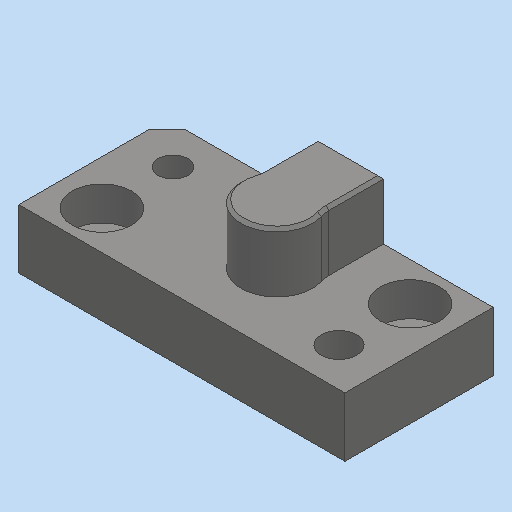
# Autodesk Inventor part: MM0948AN160_G01_155
Saved by Autodesk Inventor 2023.3 (Build 273359000, 359)
## iProperties
RuleStatus: InUse
Created: 2023-04-14
Part Number: MM0948AN160_G01_155
Material: 1.2379 X155CrVMo12-1
Description: =<RBPARTNOTITLE2>
Document SubType Name: Modeling
Designer: ric7an
Mass: 110.504 g
Surface Area: 55.1793 cm^2
Volume: 14.0769 cm^3
Density: 7.85 g/cm^3
Appearance: Stahl - rostfrei AnP
AnP_Kategorie: 1
AnP_Material: =<Material>
MaxAbmaße: 20 x 25 x 55 (FM)
AnP_TemplVers: 20200821
RBDOCUMENTTYPE: DRF
RBDOCUMENTVERSION: 00
RBDRAWINGMAINSCALE: 1:1
RBDRAWINGMISSINGSPEC: --
RBDRAWINGVOLUME: --
RBDSV1: 0850
RBGBEDGESIN1: +0,5
RBGBEDGESIN2: +0,2
RBGBEDGESOUT1: -0,3
RBGBEDGESOUT2: -0,1
RBMATERIAL: =<Material>
RBMATMEETS: --
RBMATNO: =<Part Number>
RBPARTMADEOF: 20 x 25 x 55 (FM)
RBPARTNO: SIEHE MNR
RBPARTNOTITLE1: manufactured part
RBPARTNOTITLE2: Anfertigungsteil
RBPARTSAFETYINDICATOR: --
RBSURFACE: vaccum hardened 58 HRC ± 1
RBSURFACE2: vakuumgehaertet 58 HRC ± 1
RBZEDGESNORM: ISO13715:2002-06
RBZGENDIMCLASS: m
RBZGENDIMNORM: ISO 2768-1:1989-11
RBZGENGEOCLASS: H
RBZGENGEONORM: ISO 2768-2:1989-11
RBZSURFACENORM: ISO13D2:2002-02
RBZTOLERANCENORM: ISO 14405-1:2010-12
Author: ric7an
Keywords: =<RBPARTMADEOF>
Comments: =<RBSURFACE2>
Revision Number: 01
Autodesk Inventor part; units mm, degrees
ref_plane "YZ Plane" through (0, 0, 0) normal (1, 0, 0) x (0, 1, 0)
ref_plane "XZ Plane" through (0, 0, 0) normal (0, 1, 0) x (-1, 0, 0)
ref_plane "XY Plane" through (0, 0, 0) normal (0, 0, 1) x (1, 0, 0)
sketch "Skizze1" plane through (0, 0, 0) normal (0, 0, 1) x (1, 0, 0)
  line L0 (-27.5, 12.5) -> (27.5, 12.5)
  line L1 (27.5, 12.5) -> (27.5, -12.5)
  line L2 (27.5, -12.5) -> (-27.5, -12.5)
  line L3 (-27.5, -12.5) -> (-27.5, 12.5)
  line L4 (0, 17.5) -> (0, -17.5) projected
  line L5 (-38.5, 0) -> (38.5, 0) projected
  point P0 (0, 0)
  dimension "d0" = 55
  dimension "d1" = 25
  constraints: 8 end point, 2 parallel, 1 horizontal, 1 perpendicular, 2 other
  measures "d0" distance of L0.start L0.end
  measures "d1" distance of L0.end L1.end
extrude "Extrusion1" add sketch "Skizze1" along normal blind 10
sketch "Skizze2" plane through (0, 0, 10) normal (0, 0, 1) x (1, 0, 0)
  line L0 (0, 17.5) -> (0, -17.5) projected
  line L1 (-38.5, 0) -> (38.5, 0) projected
  point P0 (0, 0)
  point P1 (-20, -6)
  point P2 (20, 6)
  dimension "d4" = 40
  dimension "d5" = 20
  dimension "d6" = 12
  dimension "d7" = 6
  measures "d4" horizontal distance of point (20, 6) point (-20, -6)
  measures "d5" distance from line of L0 point (-20, -6)
  measures "d6" vertical distance of point (20, 6) point (-20, -6)
  measures "d7" distance from line of L1 point (-20, -6)
hole "Bohrung1" at (-20, -6, 10) at (20, 6, 10) direction (0, 0, -1) diameter 5.5 end through all counterbore diameter 10 counterbore depth 5.7 clearance for "Inbusschraube ISO 4762  versenkt" size "M5" standard "ISO"
sketch "Skizze3" plane through (0, 0, 10) normal (0, 0, 1) x (1, 0, 0)
  circle A0 centre (-20, -6) radius 5 projected
  circle A1 centre (20, 6) radius 5 projected
  point P0 (0, 0)
  point P1 (-20, 6)
  constraints: 1 horizontal alignment, 1 vertical alignment
hole "Bohrung2" at (-20, 6, 10) direction (0, 0, -1) diameter 5 end through all
sketch "Skizze4" plane through (0, 0, 10) normal (0, 0, 1) x (1, 0, 0)
  circle A0 centre (-20, 6) radius 2.5 projected
  circle A1 centre (-20, -6) radius 5 projected
  circle A2 centre (20, 6) radius 5 projected
  line L0 (27.5, -12.5) -> (27.5, 12.5) projected
  line L1 (27.5, 12.5) -> (-27.5, 12.5) projected
  line L2 (-27.5, 12.5) -> (-27.5, -12.5) projected
  line L3 (-27.5, -12.5) -> (27.5, -12.5) projected
  point P0 (0, 0)
  point P1 (20, -6)
  constraints: 1 horizontal alignment, 1 vertical alignment
hole "Bohrung3" at (20, -6, 10) direction (0, 0, -1) diameter 6 end through all
sketch "Skizze5" plane through (0, 0, 10) normal (0, 0, 1) x (1, 0, 0)
  line L0 (-27.5, -12.5) -> (27.5, -12.5) projected
  line L1 (27.5, -12.5) -> (27.5, 12.5) projected
  circle A0 centre (3.5, 0) radius 6
  line L2 (27.5, 12.5) -> (-27.5, 12.5) projected
  line L3 (-2, 12.5) -> (9, 12.5)
  line L4 (9, 12.5) -> (9, 2.3979)
  line L5 (9, 2.3979) -> (-2, 2.3979)
  line L6 (-2, 2.3979) -> (-2, 12.5)
  point P0 (0, 0)
  point P1 (3.5, 0)
  dimension "d29" = 12.5
  dimension "d30" = 24
  dimension "d42" = 12
  dimension "d47" = 11
  constraints: 8 end point, 2 parallel, 2 point on circle, 1 centre point, 1 coincident, 1 horizontal, 1 perpendicular, 1 point on line
  measures "d29" distance from line of L0 point (3.5, 0)
  measures "d30" distance from line of L1 point (3.5, 0)
  measures "d42" diameter of A0
  measures "d47" distance between parallel lines of L4 L6
chamfer "Fase1" distance 3 angle 45 1 edges at (-27.5, 12.5, 5)
extrude "Extrusion2" add sketch "Skizze5" along normal blind 10
fillet "Rundung1" radius 5 2 edges at (9, 2.3979, 15) (-2, 2.3979, 15)
chamfer "Fase2" distance 0.5 angle 45 6 edges at (9, 7.8894, 20) (9.0571, 2.5249, 20) (3.5, -6, 20) (-2.0571, 2.5249, 20) (-2, 7.8894, 20) (3.5, 12.5, 20)
equation "\"d5\" = 0.5 * d4"
equation "\"d7\" = 0.5 * d6"
